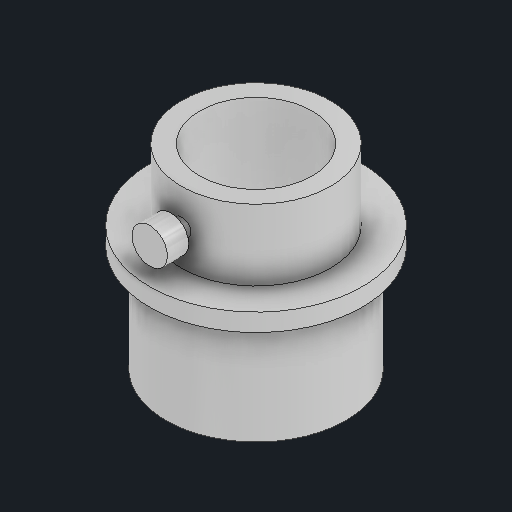
# Autodesk Inventor part: c8n_adapter_125
Saved by Autodesk Inventor 2027.1 (Build 311270010, 270A)
## iProperties
Created: 2026-11-04
Part Number: c8n_adapter_125
Material: Generic
Description: 2 in to 1.25 in adapter
Document SubType Name: Modeling
Designer: Claude (from photos)
Density: 1 g/cm^3
Appearance: Aluminum - Polished
Author: alexg
Autodesk Inventor part; units mm, degrees
ref_plane "Work Plane1" through (0, 170, 0) normal (0, 1, 0) x (-1, 0, 0)
sketch "2 in barrel sketch" plane through (0, 170, 0) normal (0, 1, 0) x (-1, 0, 0)
  circle A0 centre (-842, 0) radius 25.4
  circle A1 centre (-842, 0) radius 15.9
  constraints: 2 centre point
extrude "2 in barrel" add sketch "2 in barrel sketch" along normal blind 30
ref_plane "Work Plane2" through (0, 200, 0) normal (0, 1, 0) x (-1, 0, 0)
sketch "Flange sketch" plane through (0, 200, 0) normal (0, 1, 0) x (-1, 0, 0)
  circle A0 centre (-842, 0) radius 30
  circle A1 centre (-842, 0) radius 15.9
  constraints: 2 centre point
extrude "Flange" add sketch "Flange sketch" along normal blind 5
ref_plane "Work Plane3" through (0, 205, 0) normal (0, 1, 0) x (-1, 0, 0)
sketch "1.25 in holder sketch" plane through (0, 205, 0) normal (0, 1, 0) x (-1, 0, 0)
  circle A0 centre (-842, 0) radius 21
  circle A1 centre (-842, 0) radius 15.9
  constraints: 2 centre point
extrude "1.25 in holder" add sketch "1.25 in holder sketch" along normal blind 20
ref_plane "Work Plane4" through (0, 0, 20) normal (0, 0, 1) x (1, 0, 0)
sketch "Screw sketch" plane through (0, 0, 20) normal (0, 0, 1) x (1, 0, 0)
  circle A0 centre (842, 215) radius 2.5
  constraints: 1 centre point
extrude "Screw" add sketch "Screw sketch" along normal blind 6
ref_plane "Work Plane5" through (0, 0, 24) normal (0, 0, 1) x (1, 0, 0)
sketch "Thumbscrew sketch" plane through (0, 0, 24) normal (0, 0, 1) x (1, 0, 0)
  circle A0 centre (842, 215) radius 5
  constraints: 1 centre point
extrude "Thumbscrew" add sketch "Thumbscrew sketch" along normal blind 6
body "Solid1"
